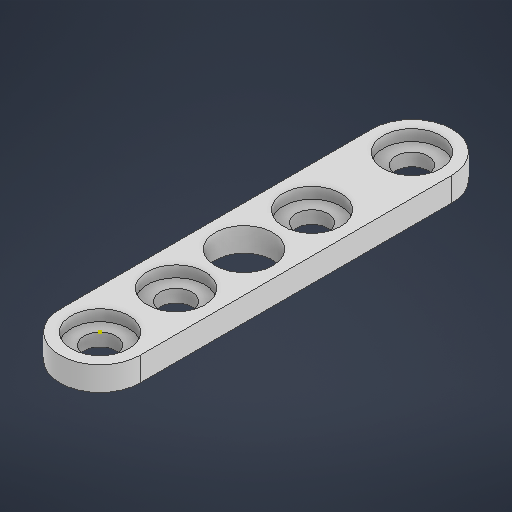
# Autodesk Inventor part: trzymanie_kola1
Saved by Autodesk Inventor 2026.1 (Build 301233020, 233B)
## iProperties
Created: 2026-07-11
Part Number: trzymanie_kola1
Material: Ogólny
Document SubType Name: Modeling
Designer: Nitro
Density: 1 g/cm^3
Appearance: Domyślna
Author: Nitro
Autodesk Inventor part; units mm, degrees
ref_plane "YZ Plane" through (0, 0, 0) normal (1, 0, 0) x (0, 1, 0)
ref_plane "XZ Plane" through (0, 0, 0) normal (0, 1, 0) x (-1, 0, 0)
ref_plane "XY Plane" through (0, 0, 0) normal (0, 0, 1) x (1, 0, 0)
sketch "Szkic1" plane through (0, 0, 0) normal (0, 1, 0) x (-1, 0, 0)
  line L0 (0, 0) -> (0, -39) construction
  line L1 (-5, 0) -> (-5, -39)
  line L2 (5, -39) -> (5, 0)
  arc A0 (5, 0) -> (-5, 0) centre (0, 0) ccw
  arc A1 (-5, -39) -> (5, -39) centre (0, -39) ccw
  point P0 (0, -19.5)
  dimension "d0" = 39
  dimension "d1" = 10
  constraints: 8 end point, 4 point on circle, 4 tangent, 2 centre point, 1 midpoint, 1 parallel, 1 vertical
  measures "d0" distance of L0.start L0.end
  measures "d1" diameter of A1
extrude "Wyciągnięcie proste1" add sketch "Szkic1" along normal blind 2
sketch "Szkic7" plane through (0, 2, 0) normal (0, 1, 0) x (1, 0, 0)
  point P0 (0, 0)
  point P1 (0, 0)
  point P2 (0, 39)
  dimension "d32" = 39
  constraints: 1 coincident
  measures "d32" distance of point (0, 39) point (0, 0)
hole "Otwór3" at (0, 2, 0) at (0, 2, -39) direction (0, -1, 0) diameter 3 depth 10
sketch "Szkic8" plane through (0, 2, 0) normal (0, 1, 0) x (1, 0, 0)
  circle A0 centre (0, 39) radius 1.5 projected
  circle A1 centre (0, 0) radius 1.5 projected
  arc A2 (5, 39) -> (-5, 39) centre (0, 39) ccw projected
  line L0 (-5, 39) -> (-5, 0) projected
  arc A3 (-5, 0) -> (5, 0) centre (0, 0) ccw projected
  line L1 (5, 0) -> (5, 39) projected
  circle A4 centre (0, 0) radius 2.35
  circle A5 centre (0, 39) radius 2.35
  dimension "d40" = 4.7
  dimension "d41" = 4.7
  constraints: 2 centre point, 2 coincident
  measures "d40" diameter of A4
  measures "d41" diameter of A5
extrude "Wyciągnięcie proste4" cut sketch "Szkic8" against normal blind 0.4 contours A0 | A1 | A4 | A5
sketch "Szkic9" plane through (0, 2, 0) normal (0, 1, 0) x (1, 0, 0)
  circle A0 centre (0, 0) radius 2.35 projected
  circle A1 centre (0, 39) radius 2.35 projected
  arc A2 (5, 39) -> (-5, 39) centre (0, 39) ccw projected
  line L0 (-5, 39) -> (-5, 0) projected
  arc A3 (-5, 0) -> (5, 0) centre (0, 0) ccw projected
  line L1 (5, 0) -> (5, 39) projected
  point P0 (0, 9.5)
  point P1 (0, 26.5)
  dimension "d44" = 9.5
  dimension "d45" = 12.5
  measures "d44" distance of point (0, 0) point (0, 9.5)
  measures "d45" distance of point (0, 26.5) A1.centre
hole "Otwór4" at (0, 2, -9.5) at (0, 2, -26.5) direction (0, -1, 0) diameter 4 depth 10
sketch "Szkic10" plane through (0, 2, 0) normal (0, 1, 0) x (1, 0, 0)
  circle A0 centre (0, 26.5) radius 2 projected
  circle A1 centre (0, 9.5) radius 2 projected
  circle A2 centre (0, 0) radius 2.35 projected
  circle A3 centre (0, 39) radius 2.35 projected
  arc A4 (5, 39) -> (-5, 39) centre (0, 39) ccw projected
  line L0 (-5, 39) -> (-5, 0) projected
  arc A5 (-5, 0) -> (5, 0) centre (0, 0) ccw projected
  line L1 (5, 0) -> (5, 39) projected
  circle A6 centre (0, 9.5) radius 3.6
  circle A7 centre (0, 26.5) radius 3.6
  dimension "d53" = 7.2
  dimension "d54" = 7.2
  constraints: 2 centre point, 2 coincident
  measures "d53" diameter of A6
  measures "d54" diameter of A7
extrude "Wyciągnięcie proste5" cut sketch "Szkic10" against normal blind 0.4 contours A6 | A7
sketch "Szkic11" plane through (0, 2, 0) normal (0, 1, 0) x (1, 0, 0)
  point P0 (0, 0)
sketch "Szkic12" plane through (0, 2, 0) normal (0, 1, 0) x (1, 0, 0)
  circle A0 centre (0, 26.5) radius 3.6 projected
  circle A1 centre (0, 9.5) radius 3.6 projected
  circle A2 centre (0, 0) radius 2.35 projected
  circle A3 centre (0, 39) radius 2.35 projected
  arc A4 (5, 39) -> (-5, 39) centre (0, 39) ccw projected
  line L0 (-5, 39) -> (-5, 0) projected
  arc A5 (-5, 0) -> (5, 0) centre (0, 0) ccw projected
  line L1 (5, 0) -> (5, 39) projected
  point P0 (0, 18)
  dimension "d57" = 8.5
  measures "d57" distance of A1.centre point (0, 18)
hole "Otwór5" at (0, 2, -18) direction (0, -1, 0) diameter 7.2 depth 10
sketch "Szkic13" plane through (0, 0, 0) normal (0, -1, 0) x (1, 0, 0)
  circle A0 centre (0, -18) radius 3.6 projected
  circle A1 centre (0, -26.5) radius 2 projected
  circle A2 centre (0, -9.5) radius 2 projected
  circle A3 centre (0, -39) radius 1.5 projected
  circle A4 centre (0, 0) radius 1.5 projected
  arc A5 (-5, -39) -> (5, -39) centre (0, -39) ccw projected
  line L0 (5, 0) -> (5, -39) projected
  arc A6 (5, 0) -> (-5, 0) centre (0, 0) ccw projected
  line L1 (-5, -39) -> (-5, 0) projected
extrude "Wyciągnięcie proste6" add sketch "Szkic13" along normal blind 1.5
sketch "Szkic14" plane through (0, -1.5, 0) normal (0, -1, 0) x (1, 0, 0)
  line L0 (-5, 0) -> (-5, -39) projected
  arc A0 (-5, -39) -> (5, -39) centre (0, -39) ccw projected
  line L1 (5, -39) -> (5, 0) projected
  arc A1 (5, 0) -> (-5, 0) centre (0, 0) ccw projected
  circle A2 centre (0, -18) radius 3.6 projected
  circle A3 centre (0, -26.5) radius 2 projected
  circle A4 centre (0, -9.5) radius 2 projected
  circle A5 centre (0, 0) radius 1.5 projected
  circle A6 centre (0, -39) radius 1.5 projected
extrude "Wyciągnięcie proste7" cut sketch "Szkic14" against normal blind 0.5
sketch "Szkic15" plane through (0, 1.6, 0) normal (0, 1, 0) x (1, 0, 0)
  circle A0 centre (0, 0) radius 1.5 projected
  circle A1 centre (0, 0) radius 1.5 projected
  circle A2 centre (0, 0) radius 2.35 projected
  circle A3 centre (0, 9.5) radius 3.6 projected
  circle A4 centre (0, 9.5) radius 2 projected
  circle A5 centre (0, 26.5) radius 3.6 projected
  circle A6 centre (0, 26.5) radius 2 projected
  circle A7 centre (0, 39) radius 1.5 projected
  circle A8 centre (0, 39) radius 2.35 projected
extrude "Wyciągnięcie proste8" cut sketch "Szkic15" against normal blind 1 contours A0 | A2 | A3 | A5 | A7 | A8
sketch "Szkic16" plane through (0, 2, 0) normal (0, 1, 0) x (1, 0, 0)
  circle A0 centre (0, 0) radius 1.5 projected
  circle A1 centre (0, 0) radius 3.6
  circle A2 centre (0, 39) radius 1.5 projected
  circle A3 centre (0, 39) radius 3.6
  dimension "d71" = 7.2
  dimension "d72" = 7.2
  constraints: 2 centre point, 2 coincident
  measures "d71" diameter of A1
  measures "d72" diameter of A3
extrude "Wyciągnięcie proste9" cut sketch "Szkic16" against normal blind 1.4
sketch "Szkic17" plane through (0, 0.6, 0) normal (0, 1, 0) x (1, 0, 0)
  circle A0 centre (0, 39) radius 3.6 projected
  circle A1 centre (0, 0) radius 3.6 projected
  circle A2 centre (0, 18) radius 3.6 projected
  circle A3 centre (0, 26.5) radius 3.6 projected
  circle A4 centre (0, 9.5) radius 3.6 projected
  arc A5 (5, 39) -> (-5, 39) centre (0, 39) ccw projected
  line L0 (-5, 39) -> (-5, 0) projected
  arc A6 (-5, 0) -> (5, 0) centre (0, 0) ccw projected
  line L1 (5, 0) -> (5, 39) projected
  circle A7 centre (0, 0) radius 2
  circle A8 centre (0, 39) radius 2
  dimension "d75" = 4
  dimension "d76" = 4
  constraints: 2 centre point, 2 coincident
  measures "d75" diameter of A7
  measures "d76" diameter of A8
extrude "Wyciągnięcie proste10" cut sketch "Szkic17" against normal blind 10 contours A7 | A8
